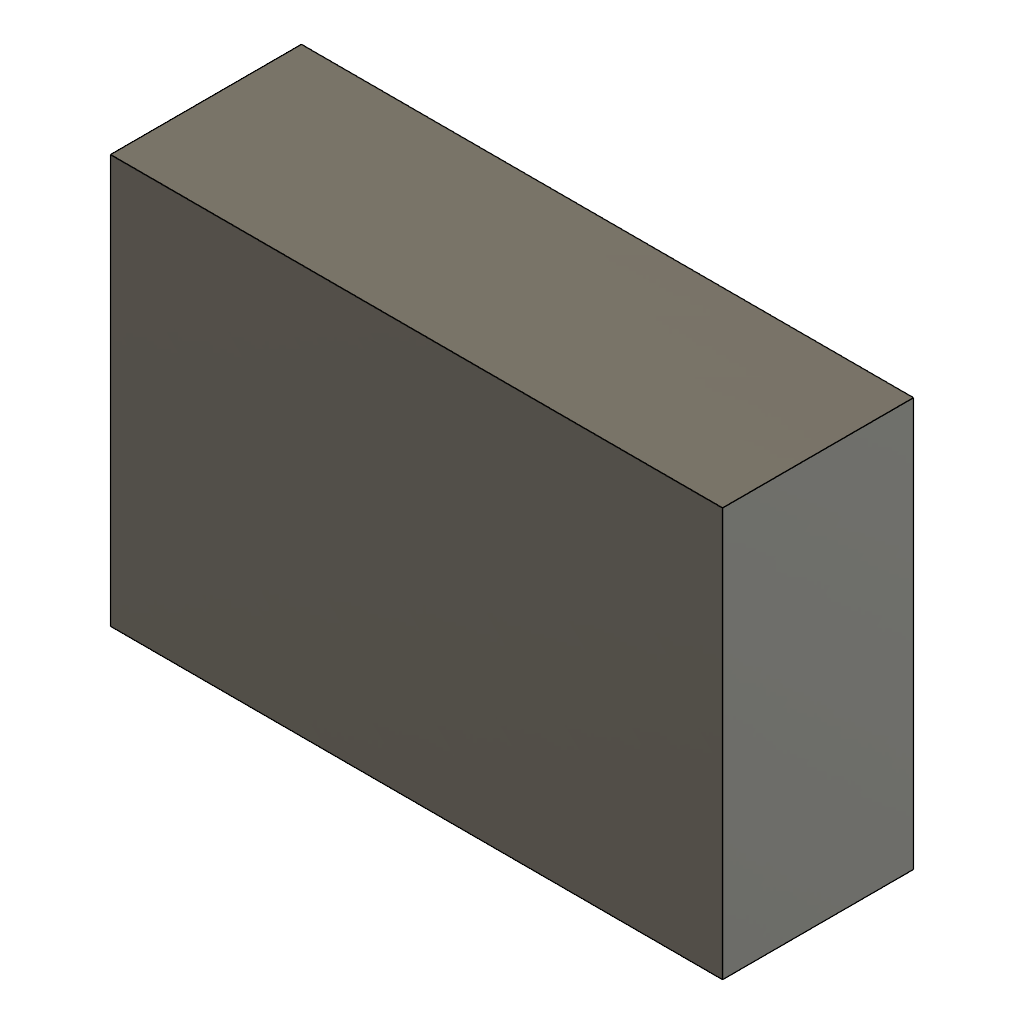
BossReverseXYHoldout (Autodesk Fusion 360 design; units mm, degrees)
part number: 2026-11-23-18-17-31-621
Autodesk Fusion 360 part; units mm, degrees
sketch "RectangleSketch" plane through (0, 0, 0) normal (0, 0, 1) x (1, 0, 0)
  line L0 (0, 0) -> (43.9, 0)
  line L1 (43.9, 0) -> (43.9, 29.3)
  line L2 (43.9, 29.3) -> (0, 29.3)
  line L3 (0, 29.3) -> (0, 0)
  dimension "width_mm" = 43.9
  dimension "height_mm" = 29.3
  constraint horizontal L0
  constraint vertical L1
  constraint horizontal L2
  constraint vertical L3
  constraint coincident L0.start L3.end
  measures "width_mm" horizontal distance of L0.start L0.end
  measures "height_mm" vertical distance of L0.start L2.end
extrude "BlindBoss" add sketch "RectangleSketch" against normal blind 13.7
equation "depth_mm = -13.700000000000001 mm"
